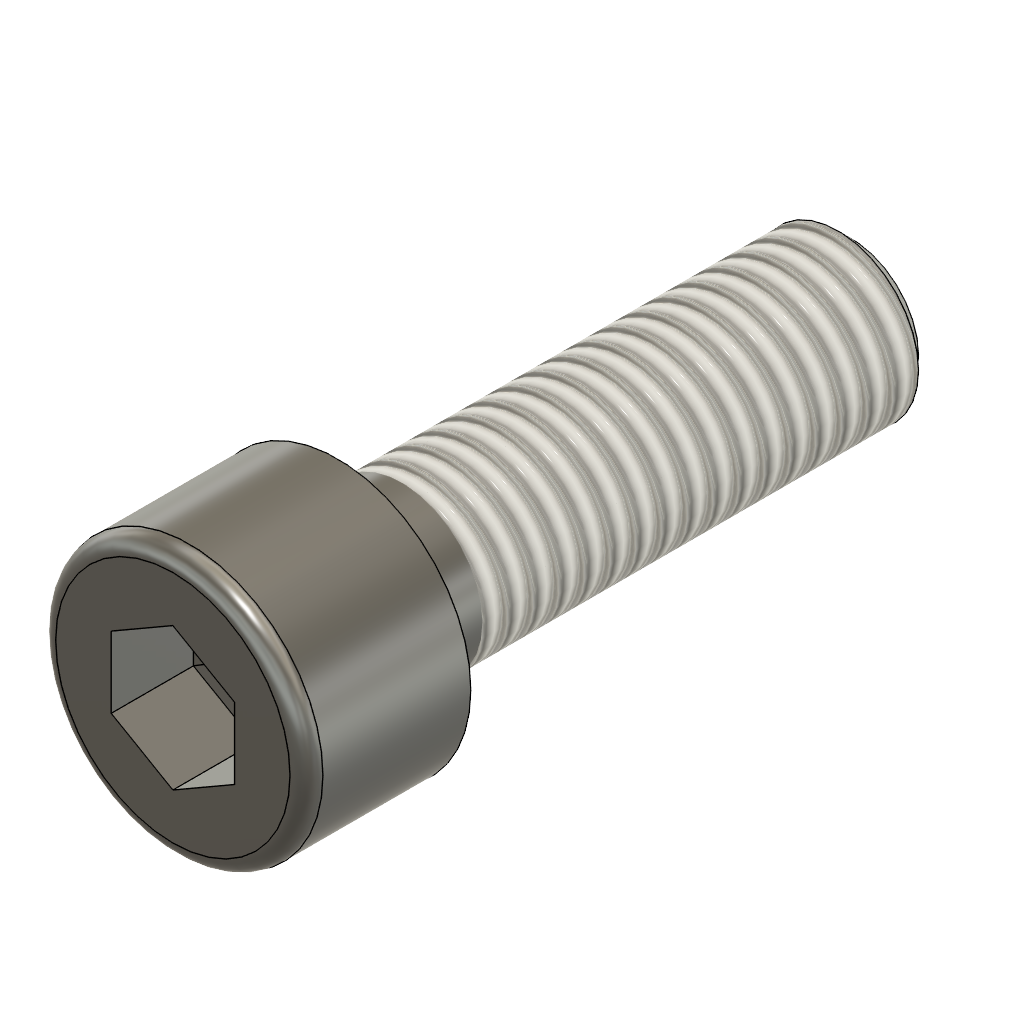
Bike Stem (Assembly) (Autodesk Fusion 360 archive; units mm, degrees)
design "Hexagon Socket Head Cap Screw ISO 4762 - M8 x 25 Steel 4.6 Plain"
description: Hexagon Socket Head Cap Screw ISO 4762 - M8 x 25
part number: ISO 4762 - M8 x 25 Steel 4.6 Plain
Autodesk Fusion 360 part; units mm, degrees
sketch "Sketch1" plane through (0, 0, 0) normal (0, 1, 0) x (1, 0, 0)
  line L0 (-4, 0) -> (-4, 25)
  line L1 (-4, 25) -> (0, 25)
  line L2 (0, 25) -> (0, -8)
  line L3 (-4, 0) -> (-6.5, 0)
  line L4 (-6.5, 0) -> (-6.5, -8)
  line L5 (-6.5, -8) -> (0, -8)
  dimension "d9" = 8
  dimension "d106" = 8
  dimension "d107" = 25
  dimension "d116" = 13
  constraint perpendicular L0 L1
  constraint collinear origin L1.end L2.end
  constraint perpendicular L0 L3
  constraint coincident origin L3
  constraint vertical L2
  constraint coincident L2 L5.end
  constraint perpendicular L2 L5
  measures "d106" distance of L3 L5
  measures "d107" distance of origin L1
revolve "Revolve1" add sketch "Sketch1" angle 360 about axis through (0, 0, -25) along (0, 0, 1)
ref_plane "WorkPlane1" through (0, 0, 8) normal (0, 0, 1) x (1, 0, 0)
sketch "Sketch6" plane through (0, 0, 8) normal (0, 0, 1) x (1, 0, 0)
  line L0 (-3, 1.7321) -> (-3, -1.7321)
  line L1 (-3, -1.7321) -> (0, -3.4641)
  line L2 (0, -3.4641) -> (3, -1.7321)
  line L3 (3, -1.7321) -> (3, 1.7321)
  line L4 (3, 1.7321) -> (0, 3.4641)
  line L5 (0, 3.4641) -> (-3, 1.7321)
  dimension "d117" = 6
  constraint vertical L0
  measures "d117" distance of L0 L3
extrude "Extrude1" cut sketch "Sketch6" against normal blind 4
extrude "Extrude2" cut 1 faces at (-1, -0.5774, 4) along direction (0, 0, -1) blind 4 draft -85
fillet "Fillet4" radius 0.8 1 edges at (-6.0601, 2.3505, 8)
thread "Thread3" "ISO Metric profile 8.0 M8x1.25 M8x1.25 6g" major diameter 7.866 minor diameter 6.4455 pitch 1.25 angle 60 resizes the face on face at (-3.9801, 0.3983, -16.6667) from (0, 0, -3.125) to (0, 0, -25)
sketch "Sketch7" plane through (0, 0, 0) normal (0, 1, 0) x (1, 0, 0)
  line L0 (-4.08, 25) -> (-4.08, 24.2)
  line L1 (-4.08, 24.2) -> (-3.28, 25)
  line L2 (0, 25) -> (0, -8)
  line L3 (-4.08, 25) -> (0, 25)
  dimension "d101" = 45
  dimension "d112" = 0.8
  dimension "d113" = 4.08
  constraint coincident L2.start L3.end
  constraint perpendicular L2 L3
  constraint coincident L1.end L3
  constraint perpendicular L0 L3
  measures "d101" angle of L0 L1
  measures "d112" distance of L0.end L3
  measures "d113" distance of L0 L2.start
revolve "Revolve3" cut sketch "Sketch7" angle 360 about axis through (0, 0, 1.75) along (0, 0, 1)
equation "d9 = adsk_nomdia"
equation "adsk_nomlen = 25.00 mm"
equation "adsk_headh = 8.00 mm"
equation "adsk_headdia = 13.00 mm"
equation "adsk_nomdia = 8.00 mm"
equation "adsk_philwidth = 6.00 mm"
equation "d31 = -adsk_phildepth"
equation "adsk_phildepth = 4.00 mm"
equation "d71 = adsk_headh"
equation "d76 = -adsk_phildepth"
equation "adsk_thrlen = 21.875 mm"
equation "d86 = adsk_nomdia * 0.1"
equation "adsk_startang = 45.00 deg"
equation "d101 = adsk_startang"
equation "adsk_pitch1 = 1.25 mm"
equation "adsk_startlen = 0.80 mm"
equation "d106 = adsk_headh"
equation "d107 = adsk_nomlen"
equation "d112 = adsk_startlen"
equation "d113 = adsk_nomdia * 0.51"
equation "d115 = min(adsk_thrlen; adsk_nomlen - 0.001 mm)"
equation "d116 = adsk_headdia"
equation "d117 = adsk_philwidth"

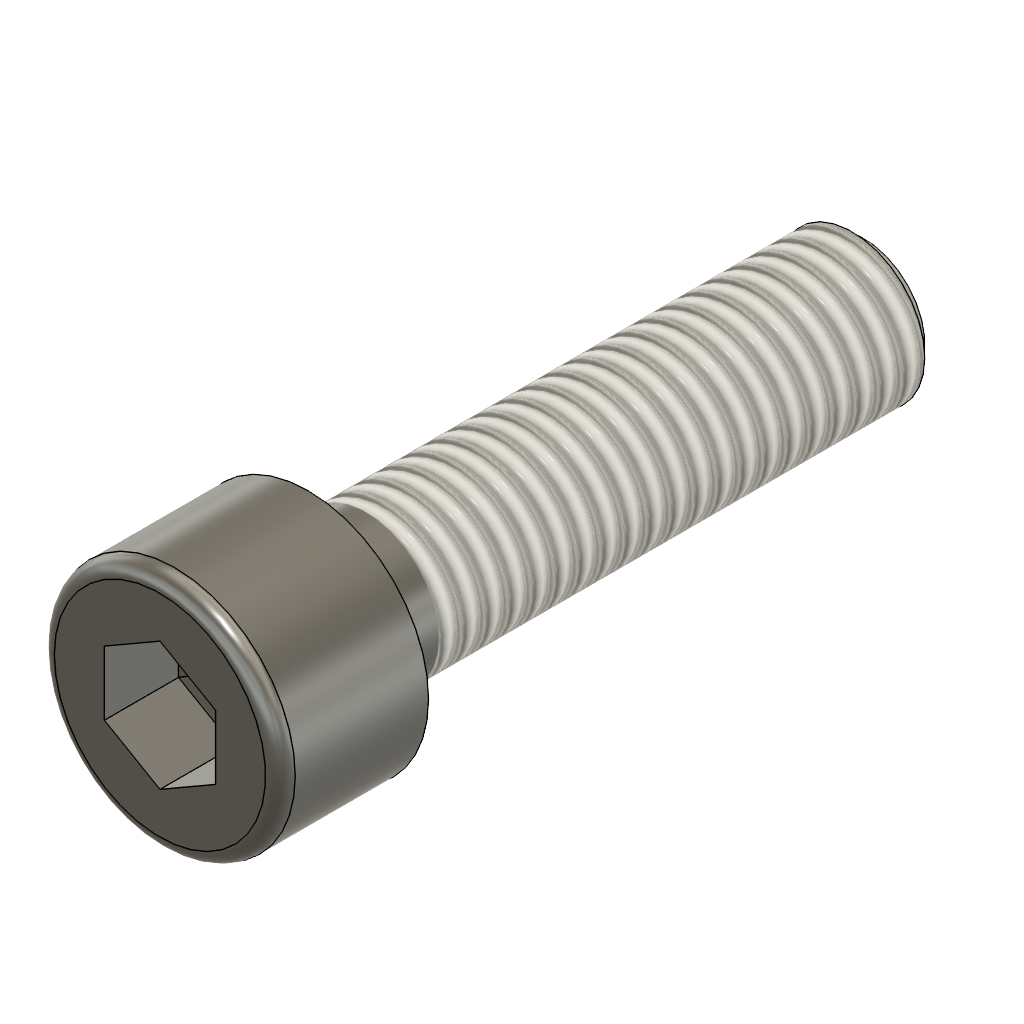
design "Hexagon Socket Head Cap Screw ISO 4762 - M8 x 30 Steel 4.6 Plain"
description: Hexagon Socket Head Cap Screw ISO 4762 - M8 x 30
part number: ISO 4762 - M8 x 30 Steel 4.6 Plain
Autodesk Fusion 360 part; units mm, degrees
sketch "Sketch1" plane through (0, 0, 0) normal (0, 1, 0) x (1, 0, 0)
  line L0 (-4, 0) -> (-4, 30)
  line L1 (-4, 30) -> (0, 30)
  line L2 (0, 30) -> (0, -8)
  line L3 (-4, 0) -> (-6.5, 0)
  line L4 (-6.5, 0) -> (-6.5, -8)
  line L5 (-6.5, -8) -> (0, -8)
  dimension "d9" = 8
  dimension "d106" = 8
  dimension "d107" = 30
  dimension "d116" = 13
  constraint perpendicular L0 L1
  constraint collinear origin L1.end L2.end
  constraint perpendicular L0 L3
  constraint coincident origin L3
  constraint vertical L2
  constraint coincident L2 L5.end
  constraint perpendicular L2 L5
  measures "d106" distance of L3 L5
  measures "d107" distance of origin L1
revolve "Revolve1" add sketch "Sketch1" angle 360 about axis through (0, 0, -30) along (0, 0, 1)
ref_plane "WorkPlane1" through (0, 0, 8) normal (0, 0, 1) x (1, 0, 0)
sketch "Sketch6" plane through (0, 0, 8) normal (0, 0, 1) x (1, 0, 0)
  line L0 (-3, 1.7321) -> (-3, -1.7321)
  line L1 (-3, -1.7321) -> (0, -3.4641)
  line L2 (0, -3.4641) -> (3, -1.7321)
  line L3 (3, -1.7321) -> (3, 1.7321)
  line L4 (3, 1.7321) -> (0, 3.4641)
  line L5 (0, 3.4641) -> (-3, 1.7321)
  dimension "d117" = 6
  constraint vertical L0
  measures "d117" distance of L0 L3
extrude "Extrude1" cut sketch "Sketch6" against normal blind 4
extrude "Extrude2" cut 1 faces at (-1, 0.5774, 4) along direction (0, 0, -1) blind 4 draft -85
fillet "Fillet4" radius 0.8 1 edges at (-6.0601, 2.3505, 8)
thread "Thread3" "ISO Metric profile 8.0 M8x1.25 M8x1.25 6g" major diameter 7.866 minor diameter 6.4455 pitch 1.25 angle 60 resizes the face on face at (-3.9801, 0.3983, -20) from (0, 0, -3.125) to (0, 0, -30)
sketch "Sketch7" plane through (0, 0, 0) normal (0, 1, 0) x (1, 0, 0)
  line L0 (-4.08, 30) -> (-4.08, 29.2)
  line L1 (-4.08, 29.2) -> (-3.28, 30)
  line L2 (0, 30) -> (0, -8)
  line L3 (-4.08, 30) -> (0, 30)
  dimension "d101" = 45
  dimension "d112" = 0.8
  dimension "d113" = 4.08
  constraint coincident L2.start L3.end
  constraint perpendicular L2 L3
  constraint coincident L1.end L3
  constraint perpendicular L0 L3
  measures "d101" angle of L0 L1
  measures "d112" distance of L0.end L3
  measures "d113" distance of L0 L2.start
revolve "Revolve3" cut sketch "Sketch7" angle 360 about axis through (0, 0, 1.75) along (0, 0, 1)
equation "d9 = adsk_nomdia"
equation "adsk_nomlen = 30.00 mm"
equation "adsk_headh = 8.00 mm"
equation "adsk_headdia = 13.00 mm"
equation "adsk_nomdia = 8.00 mm"
equation "adsk_philwidth = 6.00 mm"
equation "d31 = -adsk_phildepth"
equation "adsk_phildepth = 4.00 mm"
equation "d71 = adsk_headh"
equation "d76 = -adsk_phildepth"
equation "adsk_thrlen = 26.875 mm"
equation "d86 = adsk_nomdia * 0.1"
equation "adsk_startang = 45.00 deg"
equation "d101 = adsk_startang"
equation "adsk_pitch1 = 1.25 mm"
equation "adsk_startlen = 0.80 mm"
equation "d106 = adsk_headh"
equation "d107 = adsk_nomlen"
equation "d112 = adsk_startlen"
equation "d113 = adsk_nomdia * 0.51"
equation "d115 = min(adsk_thrlen; adsk_nomlen - 0.001 mm)"
equation "d116 = adsk_headdia"
equation "d117 = adsk_philwidth"
